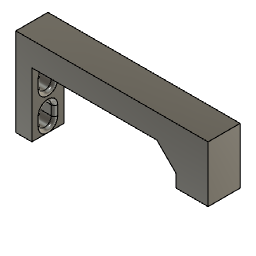
carré fixe volet SAE (Autodesk Fusion 360 design; units mm, degrees)
Autodesk Fusion 360 part; units mm, degrees
sketch "Esquisse1" plane through (0, 0, 0) normal (0, 0, 1) x (1, 0, 0)
  line L0 (0, 0) -> (10.25, 0)
  line L1 (10.25, 0) -> (10.25, -10.25)
  line L2 (10.25, -10.25) -> (0, -10.25)
  line L3 (0, -10.25) -> (0, 0)
  dimension "d1" = 10.25
  dimension "d2" = 10.25
  constraint horizontal L0
  constraint vertical L1
  constraint horizontal L2
  constraint vertical L3
  constraint coincident L0.start L3.end
  measures "d1" distance of L0.start L0.end
  measures "d2" distance of L0.start L2.end
extrude "Extrusion1" add sketch "Esquisse1" along normal blind 8 makes body 1
sketch "Esquisse2" plane through (0, 0, 8) normal (0, 0, 1) x (-1, 0, 0)
  line L0 (0, 10.25) -> (-10.25, 10.25)
  line L1 (-10.25, 10.25) -> (-10.25, 0)
  line L2 (-10.25, 0) -> (0, 0)
  line L3 (0, 0) -> (0, 10.25)
  line L4 (0, 0) -> (-10.25, 0)
  line L5 (-10.25, 0) -> (-10.25, 10.25)
  line L6 (-10.25, 10.25) -> (0, 10.25)
  line L7 (0, 10.25) -> (0, 0)
  line L8 (4.75, -5) -> (-15.25, -5)
  line L9 (-15.25, -5) -> (-15.25, 15)
  line L10 (-15.25, 15) -> (4.75, 15)
  line L11 (4.75, 15) -> (4.75, -5)
  dimension "d5" = 20
  dimension "d6" = 20
  dimension "d7" = 5
  dimension "d8" = 5
  constraint horizontal L4
  constraint vertical L5
  constraint horizontal L6
  constraint vertical L7
  constraint coincident L0.end L1.start
  constraint coincident L2.end L3.start
  constraint horizontal L8
  constraint vertical L9
  constraint horizontal L10
  constraint vertical L11
  measures "d5" distance of L8.start L8.end
  measures "d6" distance of L8.start L10.end
  measures "d7" distance of L5 L9
  measures "d8" distance of L4 L8
extrude "Extrusion2" add sketch "Esquisse2" against normal blind 10 separate body makes body 2
extrude "Extrusion3" add 2 faces at (13.5833, -3.3333, 8) (3.4167, -3.4167, 8) along direction (0, 0, 1) blind 25 separate body on bodies 1 2 makes body 3
combine "Combiner1" operation add target body 2 tool bodies 3
sketch "Esquisse3" plane through (-4.75, 0, 0) normal (-1, 0, 0) x (0, -1, 0)
  line L0 (-5, 33) -> (-5, -2)
  line L1 (-5, -2) -> (15, -2)
  line L2 (15, -2) -> (15, 33)
  line L3 (15, 33) -> (-5, 33)
  line L4 (-5, 33) -> (15, 33)
  line L5 (15, 33) -> (15, 18)
  line L6 (15, 18) -> (-5, 18)
  line L7 (-5, 18) -> (-5, 33)
  dimension "d15" = 15
  constraint horizontal L4
  constraint vertical L5
  constraint horizontal L6
  constraint vertical L7
  constraint coincident L0.start L3.end
  measures "d15" distance of L0.start L6.end
extrude "Extrusion4" add sketch "Esquisse3" along normal blind 100 contours L0 L2 L3 L4 L5 L6 L7 bodies 2
sketch "Esquisse4" plane through (0, 0, 33) normal (0, 0, 1) x (-1, 0, 0)
  line L0 (104.75, 15) -> (-15.25, 15)
  line L1 (-15.25, 15) -> (-15.25, -5)
  line L2 (-15.25, -5) -> (104.75, -5)
  line L3 (104.75, -5) -> (104.75, 15)
  line L4 (104.75, -5) -> (94.75, -5)
  line L5 (94.75, -5) -> (94.75, 15)
  line L6 (94.75, 15) -> (104.75, 15)
  line L7 (104.75, 15) -> (104.75, -5)
  dimension "d18" = 10
  constraint horizontal L4
  constraint vertical L5
  constraint horizontal L6
  constraint vertical L7
  constraint coincident L2.end L3.start
  measures "d18" distance of L2.end L4.end
extrude "Extrusion5" add sketch "Esquisse4" along normal blind 40 contours L0 L2 L3 L4 L5 L6 L7 bodies 2
sketch "Esquisse5" plane through (-94.75, 0, 0) normal (1, 0, 0) x (0, 1, 0)
  line L0 (-15, 33) -> (5, 33)
  line L1 (5, 33) -> (5, 73)
  line L2 (5, 73) -> (-15, 73)
  line L3 (-15, 73) -> (-15, 33)
  line L4 (-9.125, 67) -> (-9.125, 61)
  arc A0 (-9.125, 61) -> (-0.875, 61) centre (-5, 61) ccw
  line L5 (-0.875, 61) -> (-0.875, 67)
  arc A1 (-0.875, 67) -> (-9.125, 67) centre (-5, 67) ccw
  line L6 (-5, 67) -> (-5, 61) construction
  line L7 (-9.125, 47) -> (-9.125, 41)
  arc A2 (-9.125, 41) -> (-0.875, 41) centre (-5, 41) ccw
  line L8 (-0.875, 41) -> (-0.875, 47)
  arc A3 (-0.875, 47) -> (-9.125, 47) centre (-5, 47) ccw
  line L9 (-5, 47) -> (-5, 41) construction
  line L10 (-5, 73) -> (-5, 33) construction
  dimension "d21" = 8.25
  dimension "d22" = 8.25
  dimension "d26" = 6
  dimension "d27" = 6
  constraint tangent L4 A0
  constraint tangent A0 L5
  constraint parallel L4 L5
  constraint tangent L5 A1
  constraint tangent L4 A1
  constraint parallel L1 L6
  constraint tangent L7 A2
  constraint tangent A2 L8
  constraint parallel L7 L8
  constraint tangent L8 A3
  constraint tangent L7 A3
  constraint parallel L1 L9
  constraint midpoint L2 L10.start
  constraint midpoint L0 L10.end
  measures "d21" diameter of A0
  measures "d22" diameter of A2
  measures "d26" distance of A1.centre A0.centre
  measures "d27" distance of A3.centre A2.centre
extrude "Extrusion6" cut sketch "Esquisse5" against normal blind 15 contours L4 A0 L5 A1 | L7 A2 L8 A3 bodies 2
sketch "Esquisse6" plane through (0, 0, -2) normal (0, 0, -1) x (1, 0, 0)
  line L0 (0, 10.25) -> (10.25, 10.25)
  line L1 (10.25, 10.25) -> (10.25, 0)
  line L2 (10.25, 0) -> (0, 0)
  line L3 (-4.75, -5) -> (15.25, -5)
  line L4 (15.25, -5) -> (15.25, 15)
  line L5 (15.25, 15) -> (-4.75, 15)
  line L6 (0, 0) -> (0, 10.25)
  line L7 (-4.75, 15) -> (-4.75, -5)
fillet "Congé1" radius 2 8 edges at (-94.75, -9.125, 64) (-94.75, -5, 71.125) (-94.75, -0.875, 64) (-94.75, -5, 56.875) (-94.75, -9.125, 44) (-94.75, -5, 51.125) (-94.75, -0.875, 44) (-94.75, -5, 36.875) on bodies 2
ref_plane "Plan de construction1" through (-59.75, -5, 53) normal (1, 0, 0) x (0, 1, 0)
split "Scinder1" by plane through (-59.75, -5, 53) normal (1, 0, 0) bodies 2 makes body 4 at (8.5833, -15, 16.3333)
move_body "Déplacer1" bodies 2 to x (1, 0, 0) y (0, -1, 0) z (0, 0, -1) at (0, -10, 51)
chamfer "Chanfrein2" distance 12 angle 45 1 edges at (-4.75, -5, 18) on bodies 4
combine "Combiner2" operation add target body 4 tool bodies 2
hidden bodies 1
named bodies: "Carré volet"
